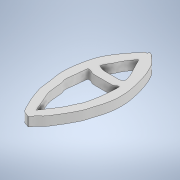
# Autodesk Inventor part: peste
Saved by Autodesk Inventor 2022.6 (Build 266554000, 554)
## iProperties
Created: 2024-11-29
Part Number: peste
Material: Generic
Document SubType Name: Modeling
Designer: Dragos Macovei
Density: 1 g/cm^3
Appearance: Default
Author: Dragos Macovei
Autodesk Inventor part; units mm, degrees
ref_plane "YZ Plane" through (0, 0, 0) normal (1, 0, 0) x (0, 1, 0)
ref_plane "XZ Plane" through (0, 0, 0) normal (0, 1, 0) x (-1, 0, 0)
ref_plane "XY Plane" through (0, 0, 0) normal (0, 0, 1) x (1, 0, 0)
sketch "Sketch1" plane through (0, 0, 0) normal (0, 1, 0) x (-1, 0, 0)
  line L0 (0, 0) -> (40, 0)
  line L1 (40, 0) -> (40, 40)
  line L2 (40, 40) -> (0, 40)
  line L3 (0, 40) -> (0, 0)
  line L4 (-185.8421, 267.0644) -> (220.5579, 267.0644) construction
  line L5 (220.5579, 267.0644) -> (220.5579, -274.8023) construction
  line L6 (220.5579, -274.8023) -> (-185.8421, -274.8023) construction
  line L7 (-185.8421, -274.8023) -> (-185.8421, 267.0644) construction
  spline S0 degree 4 poles (21.4126, 39.1261) (22.3171, 38.6414) (23.3589, 39.1076) (24.3516, 36.0822) (25.553, 34.4) (26.9543, 30.2493) (27.6366, 28.4243) (27.539, 25.8643) (28.4885, 22.2582) (28.4554, 18.9108) (26.9971, 9.9415) (24.9516, 7.6502) (22.5735, 4.036) (20.6347, 2.0964) knots 0 0 0 0 0 0.133328 0.19992 0.271287 0.343121 0.41851 0.493309 0.580004 0.67305 0.767653 1 1 1 1 1
  spline S1 degree 4 poles (20.6347, 2.0964) (20.6831, 2.0619) (20.3293, 0.9579) (19.7601, 2.076) (19.4024, 0.7169) (18.8759, 1.008) (18.8691, 1.142) (18.2624, 1.0394) (18.3464, 1.3229) knots 0 0 0 0 0 0.344029 0.480915 0.605707 0.728797 1 1 1 1 1
  spline S2 degree 4 poles (21.1785, 39.1261) (21.0742, 39.0865) (20.7987, 38.9291) (20.4783, 38.0558) (19.5649, 37.233) (18.2527, 36.1581) (17.3469, 34.2701) (16.0291, 32.4636) (15.0159, 30.3129) (13.7895, 28.3911) (13.1703, 25.3382) (12.5727, 24.1043) (12.0927, 21.8443) (11.6479, 19.7037) (11.7316, 16.5469) (11.9461, 14.2507) (13.5437, 7.9688) (15.1342, 5.1246) (15.8219, 3.1549) (18.2133, 1.7364) (18.3464, 1.3229) knots 0 0 0 0 0 0.041141 0.07612 0.119575 0.168702 0.221891 0.277912 0.335932 0.391455 0.445631 0.498778 0.551663 0.609199 0.677295 0.746917 0.814125 0.87924 1 1 1 1 1
  line L8 (21.4126, 39.1261) -> (21.1785, 39.1261)
  line L9 (24.0366, 40.2095) -> (18.3205, 38.0426) construction
  arc A0 (21.8809, 38.9061) -> (20.7985, 38.4957) centre (21.3897, 38.5691) ccw construction
  line L10 (21.6377, 36.0521) -> (21.8809, 35.7202) construction
  line L11 (21.8809, 35.7202) -> (22.2632, 34.7118) construction
  line L12 (22.2632, 34.7118) -> (23.3865, 32.1461) construction
  line L13 (23.3865, 32.1461) -> (24.1268, 30.525) construction
  line L14 (24.1268, 30.525) -> (24.5736, 29.4272) construction
  line L15 (24.5736, 29.4272) -> (24.8161, 28.7635) construction
  line L16 (24.8161, 28.7635) -> (25.0204, 27.0785) construction
  line L17 (25.0204, 27.0785) -> (25.1991, 25.5723) construction
  line L18 (25.1991, 25.5723) -> (25.1991, 24.181) construction
  line L19 (25.1991, 24.181) -> (25.5616, 23.2619) construction
  line L20 (25.5616, 23.2619) -> (25.7352, 23.0704) construction
  line L21 (25.7352, 23.0704) -> (25.8118, 21.9344) construction
  line L22 (25.8118, 21.9344) -> (25.5616, 20.4282) construction
  line L23 (25.5616, 20.4282) -> (25.3395, 18.3731) construction
  line L24 (25.3395, 18.3731) -> (25.2118, 16.9179) construction
  line L25 (25.2118, 16.9179) -> (25.0842, 15.8201) construction
  line L26 (25.0842, 15.8201) -> (24.9438, 15.6159) construction
  line L27 (24.9438, 15.6159) -> (24.4725, 15.6159) construction
  line L28 (24.4725, 15.6159) -> (23.9481, 15.7818) construction
  line L29 (23.9481, 15.7818) -> (23.361, 15.9733) construction
  line L30 (23.361, 15.9733) -> (23.361, 16.1775) construction
  line L31 (23.361, 16.1775) -> (22.5057, 16.318) construction
  line L32 (22.5057, 16.318) -> (21.8037, 16.318) construction
  line L33 (21.8037, 16.318) -> (21.3897, 16.318) construction
  line L34 (21.3897, 16.318) -> (19.7174, 16.318) construction
  line L35 (19.7174, 16.318) -> (18.3205, 16.318) construction
  line L36 (18.3205, 16.318) -> (16.7167, 16.318) construction
  line L37 (16.7167, 16.318) -> (16.0474, 16.318) construction
  line L38 (16.0474, 16.318) -> (15.5297, 16.031) construction
  line L39 (15.5297, 16.031) -> (14.9214, 15.4271) construction
  line L40 (14.9214, 15.4271) -> (14.5116, 15.7377) construction
  line L41 (14.5116, 15.7377) -> (14.6324, 16.3417) construction
  line L42 (14.6324, 16.3417) -> (14.6324, 17.6705) construction
  line L43 (14.6324, 17.6705) -> (14.7531, 19.2926) construction
  line L44 (14.7531, 19.2926) -> (14.9214, 20.2935) construction
  line L45 (14.9214, 20.2935) -> (14.9214, 21.3396) construction
  line L46 (14.9214, 21.3396) -> (15.1881, 22.3661) construction
  line L47 (15.1881, 22.3661) -> (15.3047, 23.1127) construction
  line L48 (15.3047, 23.1127) -> (15.4214, 23.9334) construction
  line L49 (15.4214, 23.9334) -> (15.6314, 24.7925) construction
  line L50 (15.6314, 24.7925) -> (15.9109, 25.5857) construction
  line L51 (15.9109, 25.5857) -> (15.9109, 26.1086) construction
  line L52 (15.9109, 26.1086) -> (16.4479, 27.0322) construction
  line L53 (16.4479, 27.0322) -> (16.7279, 27.6154) construction
  line L54 (16.7279, 27.6154) -> (17.0778, 28.2869) construction
  line L55 (17.0778, 28.2869) -> (17.5743, 29.5285) construction
  line L56 (17.5743, 29.5285) -> (18.081, 30.625) construction
  line L57 (18.081, 30.625) -> (18.7343, 31.6749) construction
  line L58 (18.7343, 31.6749) -> (19.2844, 32.4818) construction
  line L59 (19.2844, 32.4818) -> (19.7174, 33.0747) construction
  line L60 (19.7174, 33.0747) -> (20.2507, 33.7046) construction
  line L61 (20.2507, 33.7046) -> (20.4967, 34.251) construction
  line L62 (20.4967, 34.251) -> (20.7985, 34.9177) construction
  line L63 (20.7985, 34.9177) -> (21.3897, 35.571) construction
  line L64 (21.3897, 35.571) -> (21.6377, 36.0521) construction
  spline S3 degree 4 poles (21.6377, 36.0521) (21.8809, 35.7202) (22.2632, 34.7118) (23.3865, 32.1461) (24.1268, 30.525) (24.5736, 29.4272) (24.8161, 28.7635) (25.0204, 27.0785) (25.1991, 25.5723) (25.1991, 24.181) (25.5616, 23.2619) (25.7352, 23.0704) (25.8118, 21.9344) (25.5616, 20.4282) (25.3395, 18.3731) (25.2118, 16.9179) (25.0842, 15.8201) (24.9438, 15.6159) (24.4725, 15.6159) (23.9481, 15.7818) (23.361, 15.9733) (23.361, 16.1775) (22.5057, 16.318) (21.8037, 16.318) (21.3897, 16.318) (19.7174, 16.318) (18.3205, 16.318) (16.7167, 16.318) (16.0474, 16.318) (15.5297, 16.031) (14.9214, 15.4271) (14.5116, 15.7377) (14.6324, 16.3417) (14.6324, 17.6705) (14.7531, 19.2926) (14.9214, 20.2935) (14.9214, 21.3396) (15.1881, 22.3661) (15.3047, 23.1127) (15.4214, 23.9334) (15.6314, 24.7925) (15.9109, 25.5857) (15.9109, 26.1086) (16.4479, 27.0322) (16.7279, 27.6154) (17.0778, 28.2869) (17.5743, 29.5285) (18.081, 30.625) (18.7343, 31.6749) (19.2844, 32.4818) (19.7174, 33.0747) (20.2507, 33.7046) (20.4967, 34.251) (20.7985, 34.9177) (21.3897, 35.571) (21.6377, 36.0521) knots 1 1 1 1 1 2 3 4 5 6 7 8 9 10 11 12 13 14 15 16 17 18 19 20 21 22 23 24 25 26 27 28 29 30 31 32 33 34 35 36 37 38 39 40 41 42 43 44 45 46 47 48 49 50 51 52 53 53 53 53 53
  line L65 (23.8456, 12.8707) -> (23.4871, 13.0717) construction
  line L66 (23.4871, 13.0717) -> (23.1824, 13.2324) construction
  line L67 (23.1824, 13.2324) -> (22.4991, 13.4736) construction
  line L68 (22.4991, 13.4736) -> (21.7756, 13.6344) construction
  line L69 (21.7756, 13.6344) -> (20.6347, 13.6344) construction
  line L70 (20.6347, 13.6344) -> (19.4444, 13.6344) construction
  line L71 (19.4444, 13.6344) -> (18.5196, 13.6344) construction
  line L72 (18.5196, 13.6344) -> (17.3579, 13.6344) construction
  line L73 (17.3579, 13.6344) -> (16.4902, 13.6344) construction
  line L74 (16.4902, 13.6344) -> (15.9109, 13.4535) construction
  line L75 (15.9109, 13.4535) -> (15.405, 13.0516) construction
  line L76 (15.405, 13.0516) -> (15.606, 12.0668) construction
  line L77 (15.606, 12.0668) -> (15.9109, 11.1625) construction
  line L78 (15.9109, 11.1625) -> (16.1425, 10.4792) construction
  line L79 (16.1425, 10.4792) -> (16.6912, 9.394) construction
  line L80 (16.6912, 9.394) -> (16.9926, 8.8916) construction
  line L81 (16.9926, 8.8916) -> (17.3579, 8.2284) construction
  line L82 (17.3579, 8.2284) -> (17.7965, 7.3039) construction
  line L83 (17.7965, 7.3039) -> (18.3205, 6.4398) construction
  line L84 (18.3205, 6.4398) -> (18.6606, 5.5193) construction
  line L85 (18.6606, 5.5193) -> (19.0246, 4.9125) construction
  line L86 (19.0246, 4.9125) -> (19.2844, 4.7316) construction
  spline S4 degree 4 poles (23.8456, 12.8707) (23.4871, 13.0717) (23.1824, 13.2324) (22.4991, 13.4736) (21.7756, 13.6344) (20.6347, 13.6344) (19.4444, 13.6344) (18.5196, 13.6344) (17.3579, 13.6344) (16.4902, 13.6344) (15.9109, 13.4535) (15.405, 13.0516) (15.606, 12.0668) (15.9109, 11.1625) (16.1425, 10.4792) (16.6912, 9.394) (16.9926, 8.8916) (17.3579, 8.2284) (17.7965, 7.3039) (18.3205, 6.4398) (18.6606, 5.5193) (19.0246, 4.9125) (19.2844, 4.7316) knots 1 1 1 1 1 2 3 4 5 6 7 8 9 10 11 12 13 14 15 16 17 18 19 20 20 20 20 20
  line L87 (23.8456, 12.8707) -> (23.7865, 12.515) construction
  line L88 (23.7865, 12.515) -> (23.574, 11.8436) construction
  line L89 (23.574, 11.8436) -> (23.091, 11.013) construction
  line L90 (23.091, 11.013) -> (22.6606, 10.2533) construction
  line L91 (22.6606, 10.2533) -> (22.1451, 9.394) construction
  line L92 (22.1451, 9.394) -> (21.8809, 8.5987) construction
  line L93 (21.8809, 8.5987) -> (21.4126, 7.7023) construction
  line L94 (21.4126, 7.7023) -> (20.9431, 7.0572) construction
  line L95 (20.9431, 7.0572) -> (20.4967, 6.3306) construction
  line L96 (20.4967, 6.3306) -> (19.7724, 5.4324) construction
  line L97 (19.7724, 5.4324) -> (19.2844, 4.7316) construction
  spline S5 degree 4 poles (23.8456, 12.8707) (23.7865, 12.515) (23.574, 11.8436) (23.091, 11.013) (22.6606, 10.2533) (22.1451, 9.394) (21.8809, 8.5987) (21.4126, 7.7023) (20.9431, 7.0572) (20.4967, 6.3306) (19.7724, 5.4324) (19.2844, 4.7316) knots 1 1 1 1 1 2 3 4 5 6 7 8 9 9 9 9 9
  point P0 (22.6054, 38.7112)
  point P1 (23.4871, 38.037)
  point P2 (24.4725, 36.2218)
  point P3 (25.4578, 34.251)
  point P4 (26.91, 30.4132)
  point P5 (27.4804, 28.2869)
  point P6 (27.6879, 26.1086)
  point P7 (28.2065, 22.8932)
  point P8 (28.3102, 19.0035)
  point P9 (27.1693, 12.5726)
  point P10 (25.5616, 8.6829)
  point P11 (23.4871, 5.5193)
  point P12 (20.4967, 1.7126)
  point P13 (20.0926, 1.4817)
  point P14 (19.7174, 1.4529)
  point P15 (19.2844, 0.8901)
  point P16 (19.0246, 0.9478)
  point P17 (18.8515, 1.0488)
  point P18 (18.5195, 1.1065)
  point P19 (20.4967, 38.2929)
  point P20 (19.7174, 37.3876)
  point P21 (18.5196, 36.2218)
  point P22 (17.3579, 34.4399)
  point P23 (16.1425, 32.4818)
  point P24 (15.0056, 30.4132)
  point P25 (13.8897, 28.1023)
  point P26 (13.0896, 25.4073)
  point P27 (12.6053, 23.9334)
  point P28 (12.1421, 22.0596)
  point P29 (11.7842, 19.8698)
  point P30 (11.7421, 17.1537)
  point P31 (12.1, 14.1008)
  point P32 (13.8054, 7.8685)
  point P33 (14.9214, 5.363)
  point P34 (15.9109, 3.7207)
  point P35 (17.5743, 2.0964)
  dimension "d0" = 40
  dimension "d1" = 40
  constraints: 14 horizontal, 12 end point, 5 vertical, 2 midpoint, 2 parallel, 1 centre point, 1 perpendicular, 1 point on circle, 54 other
  measures "d0" distance of L2.end L1.end
  measures "d1" distance of L1.end L0.end
extrude "Extrusion1" add sketch "Sketch1" along normal blind 3 contours S0 S1 S2 L8
body "Solid1"
